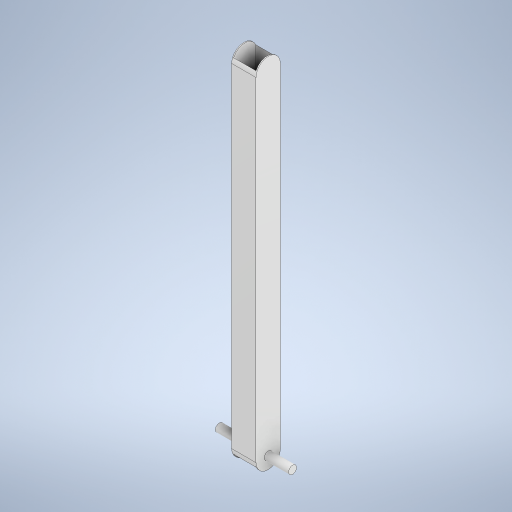
# Autodesk Inventor part: UpperArm
Saved by Autodesk Inventor 2023 (Build 270158000, 158)
## iProperties
Created: 2024-03-21
Part Number: UpperArm
Material: PVC-Piping
Document SubType Name: Modeling
Designer: BenFr
Density: 1.4 g/cm^3
Appearance: Smooth - White
Mass: 95.3836 g
Surface Area: 1012.52 cm^2
Volume: 68.1312 cm^3
Author: BenFr
Autodesk Inventor part; units mm, degrees
ref_plane "YZ Plane" through (0, 0, 0) normal (1, 0, 0) x (0, 1, 0)
ref_plane "XZ Plane" through (0, 0, 0) normal (0, 1, 0) x (-1, 0, 0)
ref_plane "XY Plane" through (0, 0, 0) normal (0, 0, 1) x (1, 0, 0)
sketch "Sketch1" plane through (0, 0, 0) normal (0, 1, 0) x (-1, 0, 0)
  line L0 (-15, 15) -> (15, 15)
  line L1 (15, 15) -> (15, -15)
  line L2 (15, -15) -> (-15, -15)
  line L3 (-15, -15) -> (-15, 15)
  line L4 (-15, 15) -> (15, -15) construction
  line L5 (15, 15) -> (-15, -15) construction
  line L6 (-13.75, 13.75) -> (13.75, 13.75)
  line L7 (13.75, 13.75) -> (13.75, -13.75)
  line L8 (13.75, -13.75) -> (-13.75, -13.75)
  line L9 (-13.75, -13.75) -> (-13.75, 13.75)
  line L10 (-13.75, 13.75) -> (13.75, -13.75) construction
  line L11 (13.75, 13.75) -> (-13.75, -13.75) construction
  point P0 (0, 0)
  dimension "d0" = 30
  dimension "d1" = 30
  dimension "d2" = 27.5
  dimension "d3" = 27.5
  constraints: 24 end point, 4 midpoint, 4 parallel, 2 horizontal, 2 perpendicular
  measures "d0" distance of L1.end L2.end
  measures "d1" distance of L0.end L1.end
  measures "d2" distance of L7.end L8.end
  measures "d3" distance of L6.end L7.end
extrude "Extrusion1" add sketch "Sketch1" along normal blind 440
fillet "Fillet1" radius 15 2 edges at (0, 0, 15) (0, 0, -15)
sketch "Sketch3" plane through (-15, 440, -15) normal (-1, 0, 0) x (0, 0, 1)
  arc A0 (0, -425) -> (30, -425) centre (15, -425) ccw projected
  line L0 (15, -440) -> (15, -425)
  circle A1 centre (15, -425) radius 5
  dimension "d7" = 15
  dimension "d8" = 10
  constraints: 2 end point, 1 centre point, 1 coincident
  measures "d7" distance of L0.start L0.end
  measures "d8" diameter of A1
extrude "Extrusion2" add sketch "Sketch3" along normal blind 30 and the other way blind 60
fillet "Fillet2" radius 15 2 edges at (0, 440, 15) (0, 440, -15)
body "Solid1"
